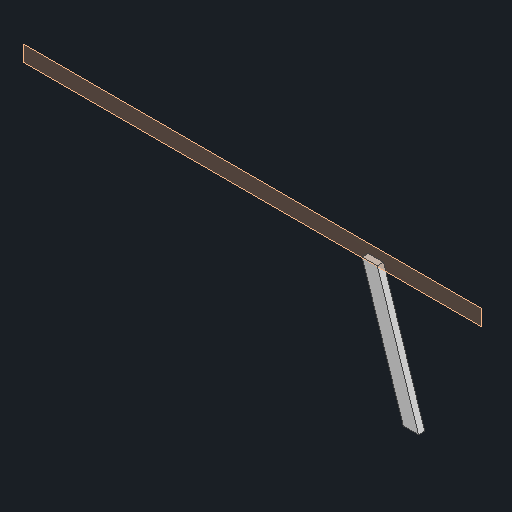
# Autodesk Inventor part: Eyelid
Saved by Autodesk Inventor 2027 (Build 310192000, 192)
## iProperties
Created: 2026-10-18
Part Number: Eyelid
Material: Generic
Document SubType Name: Modeling
Designer: lucas
Density: 1 g/cm^3
Appearance: Default
Author: lucas
Autodesk Inventor part; units mm, degrees
ref_plane "YZ Plane" through (0, 0, 0) normal (1, 0, 0) x (0, 1, 0)
ref_plane "XZ Plane" through (0, 0, 0) normal (0, 1, 0) x (-1, 0, 0)
ref_plane "XY Plane" through (0, 0, 0) normal (0, 0, 1) x (1, 0, 0)
ref_plane "Work Plane1" through (0, 0, 0) normal (0, 0, 1) x (1, 0, 0)
sketch "Sketch1" plane through (0, 0, 0) normal (0, 0, 1) x (1, 0, 0)
  line L0 (1282.7, -44.45) -> (-1282.7, -44.45) projected
  line L1 (419.1, -819.15) -> (1282.7, -819.15) projected
  line L2 (673.1, -44.45) -> (927.1, -819.15)
  line L3 (766.6563, -44.45) -> (1020.6563, -819.15)
  line L4 (673.1, -44.45) -> (766.6563, -44.45)
  line L5 (927.1, -819.15) -> (1020.6563, -819.15)
  point P0 (0, 0)
  point P1 (419.1, -44.45)
  dimension "d0" = 254
  dimension "d1" = 508
  dimension "d2" = 88.9
  constraints: 8 end point, 5 point on line, 2 collinear, 1 coincident, 1 parallel
  measures "d0" distance of L2.start point (419.1, -44.45)
  measures "d1" distance of L2.end point (419.1, -819.15)
  measures "d2" distance between parallel lines of L3 L2
extrude "Extrusion1" add sketch "Sketch1" against normal blind 38.1
body "Solid1"
